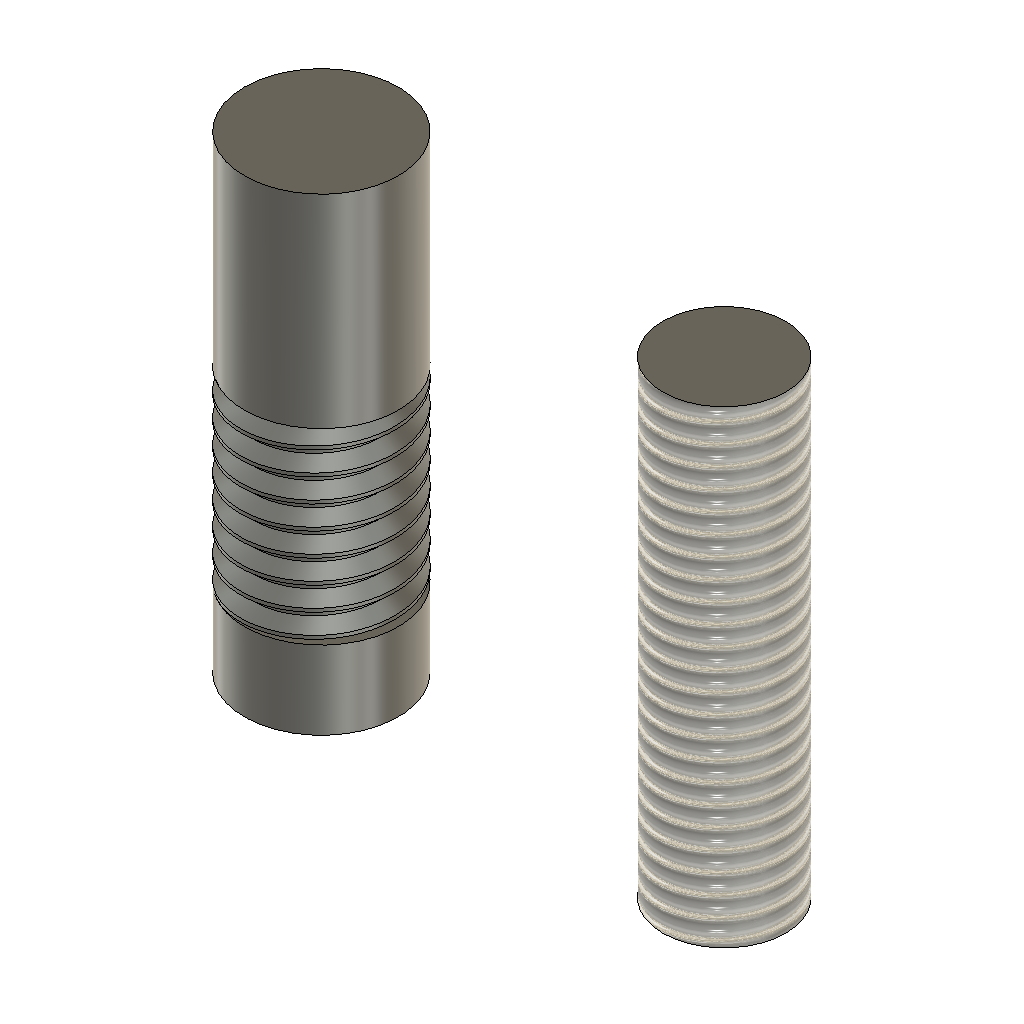
f2sc-test-threads (Autodesk Fusion 360 design; units mm, degrees)
part number: 2026-11-27-14-20-11-595
Autodesk Fusion 360 part; units mm, degrees
sketch "Sketch1" plane through (0, 0, 0) normal (0, 0, 1) x (1, 0, 0)
  circle A0 centre (0, 0) radius 5
  circle A1 centre (25.3874, 0.4051) radius 4
  dimension "d1" = 10
  dimension "d2" = 8
  constraint coincident A0.centre origin
  measures "d1" diameter of A0
  measures "d2" diameter of A1
extrude "Extrude1" add sketch "Sketch1" along normal blind 30 makes body 1 at (4.9752, -0.4978, 20) makes body 2 at (29.3675, 0.0068, 20)
thread "Thread1" "ISO Metric profile 10.0 M10x1.5 M10x1.5 6g" major diameter 9.85 minor diameter 8.141 pitch 1.5 angle 60 modelled right hand crest width 0.2177 on face at (4.9752, -0.4978, 20) from (0, 0, 5) to (0, 0, 17) crest through (4.925, 0, -0.375) on bodies 1
thread "Thread2" "ISO Metric profile 8.0 M8x1.25 M8x1.25 6g" major diameter 7.866 minor diameter 6.4455 pitch 1.25 angle 60 resizes the face on face at (29.3675, 0.0068, 20) on bodies 2
